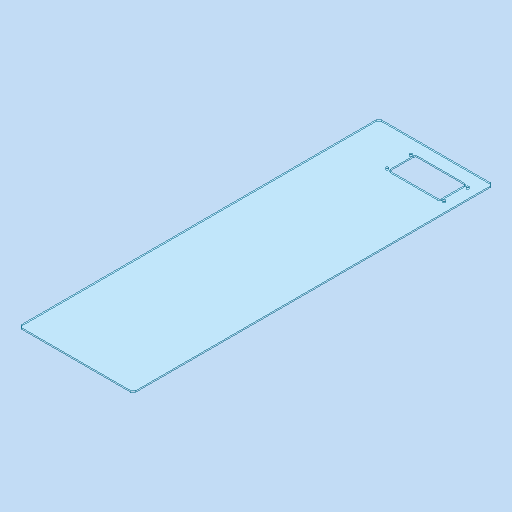
# Autodesk Inventor part: MM0948AN140_G01_109
Saved by Autodesk Inventor 2023.3 (Build 273359000, 359)
## iProperties
Part Number: MM0948AN140_G01_109
Material: Kst - PC (Eslon, klar)
Description: =<RBPARTNOTITLE2>
Document SubType Name: Modeling
Designer: ric7an
Mass: 723.095 g
Surface Area: 4093.1 cm^2
Volume: 602.579 cm^3
Density: 1.2 g/cm^3
Appearance: Klar AnP
Created: 2023-03-23
RBDOCUMENTTYPE: DRF
RBDOCUMENTVERSION: 00
RBDRAWINGMAINSCALE: 1:1
RBDRAWINGMISSINGSPEC: --
RBDRAWINGVOLUME: --
RBGBEDGESIN1: +0,5
RBGBEDGESIN2: +0,2
RBGBEDGESOUT1: -0,3
RBGBEDGESOUT2: -0,1
RBMATERIAL: =<Material>
RBMATMEETS: --
RBMATNO: =<Part Number>
RBPARTMADEOF: 3 x 809 x 257 (FM)
RBPARTNO: SIEHE MNR
RBPARTNOTITLE1: manufactured part
RBPARTNOTITLE2: Anfertigungsteil
RBPARTSAFETYINDICATOR: --
RBSURFACE: --
RBSURFACE2: --
RBZEDGESNORM: ISO13715:2002-06
RBZGENDIMCLASS: m
RBZGENDIMNORM: ISO 2768-1:1989-11
RBZGENGEOCLASS: H
RBZGENGEONORM: ISO 2768-2:1989-11
RBZSURFACENORM: ISO13D2:2002-02
RBZTOLERANCENORM: ISO 14405-1:2010-12
AnP_Material: =<Material>
AnP_TemplVers: 20190222
AnP_Kategorie: 1
MaxAbmaße: 3 x 809 x 257 (FM)
AnP_Kommentar_aktuell: =<Comments>
AnP_Material_aktuell: =<Material>
Author: FH/Wi
Keywords: =<RBPARTMADEOF>
Comments: =<RBSURFACE2>
Revision Number: 01
Autodesk Inventor part; units mm, degrees
ref_plane "YZ Plane" through (0, 0, 0) normal (1, 0, 0) x (0, 1, 0)
ref_plane "XZ Plane" through (0, 0, 0) normal (0, 1, 0) x (-1, 0, 0)
ref_plane "XY Plane" through (0, 0, 0) normal (0, 0, 1) x (1, 0, 0)
sketch "Skizze1" plane through (0, 0, 0) normal (0, 0, 1) x (1, 0, 0)
  line L0 (-128.5, 404.5) -> (128.5, 404.5)
  line L1 (128.5, 404.5) -> (128.5, -404.5)
  line L2 (128.5, -404.5) -> (-128.5, -404.5)
  line L3 (-128.5, -404.5) -> (-128.5, 404.5)
  line L4 (0, 566.3) -> (0, -566.3) projected
  line L5 (-179.9, 0) -> (179.9, 0) projected
  point P0 (0, 0)
  dimension "d0" = 257
  dimension "d1" = 809
  constraints: 8 end point, 2 parallel, 1 horizontal, 1 perpendicular, 2 other
  measures "d0" distance of L0.start L0.end
  measures "d1" distance of L0.end L1.end
extrude "Extrusion1" add sketch "Skizze1" along normal blind 3
sketch "Skizze3" plane through (0, 0, 3) normal (0, 0, 1) x (1, 0, 0)
  line L0 (-16.5, 374.5) -> (98.5, 374.5)
  line L1 (98.5, 374.5) -> (98.5, 314.5)
  line L2 (98.5, 314.5) -> (-16.5, 314.5)
  line L3 (-16.5, 314.5) -> (-16.5, 374.5)
  line L4 (128.5, 404.5) -> (-128.5, 404.5) projected
  line L5 (128.5, -404.5) -> (128.5, 404.5) projected
  point P0 (0, 0)
  dimension "d13" = 60
  dimension "d14" = 115
  dimension "d17" = 30
  dimension "d18" = 30
  constraints: 8 end point, 2 parallel, 1 horizontal, 1 perpendicular
  measures "d13" distance of L0.end L1.end
  measures "d14" distance of L0.start L0.end
  measures "d17" distance between parallel lines of L4 L0
  measures "d18" distance between parallel lines of L5 L1
extrude "Extrusion2" cut sketch "Skizze3" against normal through all
sketch "Skizze4" plane through (0, 0, 3) normal (0, 0, 1) x (1, 0, 0)
  line L0 (-16.5, 374.5) -> (98.5, 374.5) projected
  line L1 (-16.5, 314.5) -> (-16.5, 374.5) projected
  point P0 (0, 0)
  point P1 (-23, 371)
  point P2 (105, 371)
  point P3 (105, 318)
  point P4 (-23, 318)
  dimension "d19" = 53
  dimension "d20" = 128
  dimension "d21" = 3.5
  dimension "d22" = 6.5
  constraints: 2 horizontal alignment, 2 vertical alignment
  measures "d19" distance of point (105, 318) point (105, 371)
  measures "d20" distance of point (105, 371) point (-23, 371)
  measures "d21" distance from line of L0 point (105, 371)
  measures "d22" distance from line of L1 point (-23, 371)
hole "Bohrung2" at (-23, 371, 3) at (105, 371, 3) at (105, 318, 3) at (-23, 318, 3) direction (0, 0, -1) diameter 5.5 end through all
fillet "Rundung1" radius 4 4 edges at (-16.5, 374.5, 1.5) (-16.5, 314.5, 1.5) (98.5, 374.5, 1.5) (98.5, 314.5, 1.5)
chamfer "Fase1" distance 6 angle 45 4 edges at (-128.5, -404.5, 1.5) (128.5, -404.5, 1.5) (128.5, 404.5, 1.5) (-128.5, 404.5, 1.5)
